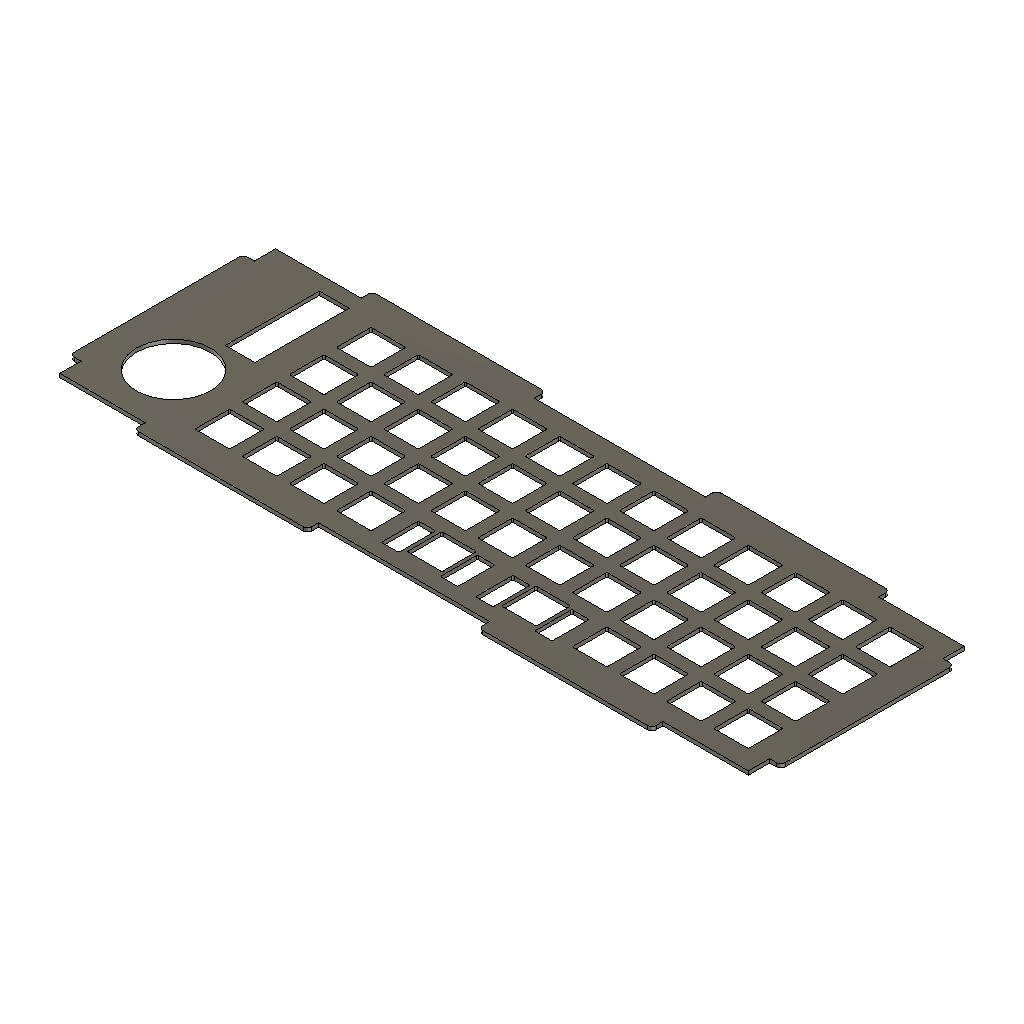
pcbPlate (Autodesk Fusion 360 design; units mm, degrees)
Autodesk Fusion 360 part; units mm, degrees
sketch "keyboard-plate" plane through (0, 0, 0) normal (0, 0, 1) x (1, 0, 0)
  line L0 (32.55, -57.15) -> (19.55, -57.15)
  arc A0 (57.65, -57.15) -> (57.15, -57.65) centre (57.65, -57.65) ccw
  line L1 (52.1, -70.65) -> (52.1, -57.65)
  line L2 (51.6, -57.15) -> (38.6, -57.15)
  line L3 (38.1, -57.65) -> (38.1, -70.65)
  arc A1 (57.15, -70.65) -> (57.65, -71.15) centre (57.65, -70.65) ccw
  arc A2 (38.6, -57.15) -> (38.1, -57.65) centre (38.6, -57.65) ccw
  line L4 (85.725, -57.65) -> (85.725, -70.65)
  line L5 (0, -57.65) -> (0, -70.65)
  arc A3 (19.05, -32.55) -> (19.55, -33.05) centre (19.55, -32.55) ccw
  arc A4 (70.65, -71.15) -> (71.15, -70.65) centre (70.65, -70.65) ccw
  line L6 (70.65, -57.15) -> (57.65, -57.15)
  arc A5 (19.55, -57.15) -> (19.05, -57.65) centre (19.55, -57.65) ccw
  arc A6 (52.1, -57.65) -> (51.6, -57.15) centre (51.6, -57.65) ccw
  line L7 (71.15, -70.65) -> (71.15, -57.65)
  line L8 (57.15, -57.65) -> (57.15, -70.65)
  line L9 (57.65, -71.15) -> (70.65, -71.15)
  arc A7 (71.15, -57.65) -> (70.65, -57.15) centre (70.65, -57.65) ccw
  line L10 (86.225, -71.15) -> (99.225, -71.15)
  arc A8 (99.725, -57.65) -> (99.225, -57.15) centre (99.225, -57.65) ccw
  arc A9 (19.05, -70.65) -> (19.55, -71.15) centre (19.55, -70.65) ccw
  arc A10 (85.725, -70.65) -> (86.225, -71.15) centre (86.225, -70.65) ccw
  arc A11 (0.5, -57.15) -> (0, -57.65) centre (0.5, -57.65) ccw
  arc A12 (38.1, -70.65) -> (38.6, -71.15) centre (38.6, -70.65) ccw
  line L11 (38.6, -71.15) -> (51.6, -71.15)
  arc A13 (99.225, -71.15) -> (99.725, -70.65) centre (99.225, -70.65) ccw
  line L12 (19.55, -71.15) -> (32.55, -71.15)
  line L13 (33.05, -70.65) -> (33.05, -57.65)
  arc A14 (33.05, -57.65) -> (32.55, -57.15) centre (32.55, -57.65) ccw
  arc A15 (32.55, -71.15) -> (33.05, -70.65) centre (32.55, -70.65) ccw
  line L14 (99.725, -70.65) -> (99.725, -57.65)
  line L15 (19.05, -57.65) -> (19.05, -70.65)
  arc A16 (51.6, -71.15) -> (52.1, -70.65) centre (51.6, -70.65) ccw
  arc A17 (165.9, -33.05) -> (166.4, -32.55) centre (165.9, -32.55) ccw
  line L16 (19.55, -33.05) -> (32.55, -33.05)
  arc A18 (51.6, -33.05) -> (52.1, -32.55) centre (51.6, -32.55) ccw
  arc A19 (89.7, -33.05) -> (90.2, -32.55) centre (89.7, -32.55) ccw
  line L17 (71.15, -32.55) -> (71.15, -19.55)
  line L18 (127.8, -19.05) -> (114.8, -19.05)
  arc A20 (166.4, -19.55) -> (165.9, -19.05) centre (165.9, -19.55) ccw
  line L19 (57.65, -33.05) -> (70.65, -33.05)
  arc A21 (95.25, -32.55) -> (95.75, -33.05) centre (95.75, -32.55) ccw
  line L20 (128.3, -32.55) -> (128.3, -19.55)
  arc A22 (114.8, -19.05) -> (114.3, -19.55) centre (114.8, -19.55) ccw
  line L21 (166.4, -32.55) -> (166.4, -19.55)
  arc A23 (133.35, -32.55) -> (133.85, -33.05) centre (133.85, -32.55) ccw
  line L22 (32.55, -19.05) -> (19.55, -19.05)
  arc A24 (146.85, -33.05) -> (147.35, -32.55) centre (146.85, -32.55) ccw
  line L23 (133.35, -19.55) -> (133.35, -32.55)
  line L24 (38.1, -19.55) -> (38.1, -32.55)
  arc A25 (33.05, -19.55) -> (32.55, -19.05) centre (32.55, -19.55) ccw
  line L25 (114.8, -33.05) -> (127.8, -33.05)
  arc A26 (128.3, -19.55) -> (127.8, -19.05) centre (127.8, -19.55) ccw
  arc A27 (108.75, -33.05) -> (109.25, -32.55) centre (108.75, -32.55) ccw
  line L26 (114.3, -19.55) -> (114.3, -32.55)
  arc A28 (52.1, -19.55) -> (51.6, -19.05) centre (51.6, -19.55) ccw
  line L27 (52.1, -32.55) -> (52.1, -19.55)
  line L28 (147.35, -32.55) -> (147.35, -19.55)
  line L29 (70.65, -19.05) -> (57.65, -19.05)
  line L30 (95.25, -19.55) -> (95.25, -32.55)
  line L31 (19.05, -19.55) -> (19.05, -32.55)
  line L32 (95.75, -33.05) -> (108.75, -33.05)
  line L33 (38.6, -33.05) -> (51.6, -33.05)
  arc A29 (114.3, -32.55) -> (114.8, -33.05) centre (114.8, -32.55) ccw
  arc A30 (147.35, -19.55) -> (146.85, -19.05) centre (146.85, -19.55) ccw
  line L34 (146.85, -19.05) -> (133.85, -19.05)
  line L35 (90.2, -32.55) -> (90.2, -19.55)
  arc A31 (38.1, -32.55) -> (38.6, -33.05) centre (38.6, -32.55) ccw
  arc A32 (71.15, -19.55) -> (70.65, -19.05) centre (70.65, -19.55) ccw
  arc A33 (127.8, -33.05) -> (128.3, -32.55) centre (127.8, -32.55) ccw
  arc A34 (0.5, -19.05) -> (0, -19.55) centre (0.5, -19.55) ccw
  arc A35 (19.55, -19.05) -> (19.05, -19.55) centre (19.55, -19.55) ccw
  arc A36 (95.75, -19.05) -> (95.25, -19.55) centre (95.75, -19.55) ccw
  line L36 (133.85, -33.05) -> (146.85, -33.05)
  arc A37 (133.85, -19.05) -> (133.35, -19.55) centre (133.85, -19.55) ccw
  line L37 (51.6, -19.05) -> (38.6, -19.05)
  arc A38 (152.4, -32.55) -> (152.9, -33.05) centre (152.9, -32.55) ccw
  line L38 (33.05, -32.55) -> (33.05, -19.55)
  arc A39 (57.15, -32.55) -> (57.65, -33.05) centre (57.65, -32.55) ccw
  line L39 (0, -19.55) -> (0, -32.55)
  line L40 (152.9, -33.05) -> (165.9, -33.05)
  line L41 (165.9, -19.05) -> (152.9, -19.05)
  line L42 (76.7, -33.05) -> (89.7, -33.05)
  line L43 (108.75, -19.05) -> (95.75, -19.05)
  arc A40 (32.55, -33.05) -> (33.05, -32.55) centre (32.55, -32.55) ccw
  line L44 (76.2, -19.55) -> (76.2, -32.55)
  line L45 (0, -38.6) -> (0, -51.6)
  arc A41 (19.05, -51.6) -> (19.55, -52.1) centre (19.55, -51.6) ccw
  arc A42 (223.05, -33.05) -> (223.55, -32.55) centre (223.05, -32.55) ccw
  line L46 (52.1, -51.6) -> (52.1, -38.6)
  arc A43 (185.45, -19.55) -> (184.95, -19.05) centre (184.95, -19.55) ccw
  line L47 (0.5, -52.1) -> (13.5, -52.1)
  arc A44 (90.2, -19.55) -> (89.7, -19.05) centre (89.7, -19.55) ccw
  arc A45 (52.1, -38.6) -> (51.6, -38.1) centre (51.6, -38.6) ccw
  line L48 (184.95, -19.05) -> (171.95, -19.05)
  line L49 (51.6, -38.1) -> (38.6, -38.1)
  line L50 (38.1, -38.6) -> (38.1, -51.6)
  arc A46 (57.15, -51.6) -> (57.65, -52.1) centre (57.65, -51.6) ccw
  arc A47 (109.25, -19.55) -> (108.75, -19.05) centre (108.75, -19.55) ccw
  arc A48 (13.5, -52.1) -> (14, -51.6) centre (13.5, -51.6) ccw
  line L51 (32.55, -38.1) -> (19.55, -38.1)
  line L52 (57.65, -52.1) -> (70.65, -52.1)
  arc A49 (38.6, -38.1) -> (38.1, -38.6) centre (38.6, -38.6) ccw
  line L53 (204, -19.05) -> (191, -19.05)
  arc A50 (90.2, -38.6) -> (89.7, -38.1) centre (89.7, -38.6) ccw
  line L54 (90.2, -51.6) -> (90.2, -38.6)
  arc A51 (171.45, -32.55) -> (171.95, -33.05) centre (171.95, -32.55) ccw
  arc A52 (184.95, -33.05) -> (185.45, -32.55) centre (184.95, -32.55) ccw
  arc A53 (76.7, -19.05) -> (76.2, -19.55) centre (76.7, -19.55) ccw
  line L55 (57.15, -19.55) -> (57.15, -32.55)
  arc A54 (19.55, -38.1) -> (19.05, -38.6) centre (19.55, -38.6) ccw
  arc A55 (191, -19.05) -> (190.5, -19.55) centre (191, -19.55) ccw
  line L56 (209.55, -19.55) -> (209.55, -32.55)
  arc A56 (57.65, -19.05) -> (57.15, -19.55) centre (57.65, -19.55) ccw
  arc A57 (190.5, -32.55) -> (191, -33.05) centre (191, -32.55) ccw
  line L57 (13.5, -38.1) -> (0.5, -38.1)
  line L58 (70.65, -38.1) -> (57.65, -38.1)
  arc A58 (33.05, -38.6) -> (32.55, -38.1) centre (32.55, -38.6) ccw
  arc A59 (204.5, -19.55) -> (204, -19.05) centre (204, -19.55) ccw
  arc A60 (76.2, -32.55) -> (76.7, -33.05) centre (76.7, -32.55) ccw
  line L59 (223.55, -32.55) -> (223.55, -19.55)
  line L60 (171.95, -33.05) -> (184.95, -33.05)
  line L61 (89.7, -19.05) -> (76.7, -19.05)
  line L62 (185.45, -32.55) -> (185.45, -19.55)
  arc A61 (70.65, -33.05) -> (71.15, -32.55) centre (70.65, -32.55) ccw
  arc A62 (223.55, -19.55) -> (223.05, -19.05) centre (223.05, -19.55) ccw
  line L63 (89.7, -38.1) -> (76.7, -38.1)
  arc A63 (171.95, -19.05) -> (171.45, -19.55) centre (171.95, -19.55) ccw
  line L64 (109.25, -32.55) -> (109.25, -19.55)
  arc A64 (89.7, -52.1) -> (90.2, -51.6) centre (89.7, -51.6) ccw
  arc A65 (0, -51.6) -> (0.5, -52.1) centre (0.5, -51.6) ccw
  arc A66 (38.6, -19.05) -> (38.1, -19.55) centre (38.6, -19.55) ccw
  line L65 (19.05, -38.6) -> (19.05, -51.6)
  arc A67 (38.1, -51.6) -> (38.6, -52.1) centre (38.6, -51.6) ccw
  line L66 (190.5, -19.55) -> (190.5, -32.55)
  arc A68 (51.6, -52.1) -> (52.1, -51.6) centre (51.6, -51.6) ccw
  line L67 (171.45, -19.55) -> (171.45, -32.55)
  arc A69 (32.55, -52.1) -> (33.05, -51.6) centre (32.55, -51.6) ccw
  line L68 (204.5, -32.55) -> (204.5, -19.55)
  arc A70 (57.65, -38.1) -> (57.15, -38.6) centre (57.65, -38.6) ccw
  line L69 (210.05, -33.05) -> (223.05, -33.05)
  arc A71 (152.9, -19.05) -> (152.4, -19.55) centre (152.9, -19.55) ccw
  arc A72 (209.55, -32.55) -> (210.05, -33.05) centre (210.05, -32.55) ccw
  arc A73 (190.5, -51.6) -> (191, -52.1) centre (191, -51.6) ccw
  arc A74 (147.35, -38.6) -> (146.85, -38.1) centre (146.85, -38.6) ccw
  line L70 (223.05, -38.1) -> (210.05, -38.1)
  arc A75 (210.05, -38.1) -> (209.55, -38.6) centre (210.05, -38.6) ccw
  line L71 (209.55, -38.6) -> (209.55, -51.6)
  line L72 (33.05, -51.6) -> (33.05, -38.6)
  line L73 (191, -33.05) -> (204, -33.05)
  arc A76 (76.2, -51.6) -> (76.7, -52.1) centre (76.7, -51.6) ccw
  arc A77 (204, -33.05) -> (204.5, -32.55) centre (204, -32.55) ccw
  arc A78 (171.45, -51.6) -> (171.95, -52.1) centre (171.95, -51.6) ccw
  arc A79 (109.25, -38.6) -> (108.75, -38.1) centre (108.75, -38.6) ccw
  arc A80 (210.05, -19.05) -> (209.55, -19.55) centre (210.05, -19.55) ccw
  line L74 (14, -51.6) -> (14, -38.6)
  arc A81 (0.5, -38.1) -> (0, -38.6) centre (0.5, -38.6) ccw
  line L75 (57.15, -38.6) -> (57.15, -51.6)
  line L76 (204, -38.1) -> (191, -38.1)
  line L77 (114.3, -38.6) -> (114.3, -51.6)
  line L78 (184.95, -38.1) -> (171.95, -38.1)
  arc A82 (114.3, -51.6) -> (114.8, -52.1) centre (114.8, -51.6) ccw
  line L79 (76.7, -52.1) -> (89.7, -52.1)
  line L80 (38.6, -52.1) -> (51.6, -52.1)
  arc A83 (204.5, -38.6) -> (204, -38.1) centre (204, -38.6) ccw
  line L81 (71.15, -51.6) -> (71.15, -38.6)
  line L82 (152.4, -19.55) -> (152.4, -32.55)
  arc A84 (171.95, -38.1) -> (171.45, -38.6) centre (171.95, -38.6) ccw
  arc A85 (152.9, -38.1) -> (152.4, -38.6) centre (152.9, -38.6) ccw
  arc A86 (70.65, -52.1) -> (71.15, -51.6) centre (70.65, -51.6) ccw
  line L83 (108.75, -38.1) -> (95.75, -38.1)
  arc A87 (191, -38.1) -> (190.5, -38.6) centre (191, -38.6) ccw
  line L84 (223.05, -19.05) -> (210.05, -19.05)
  line L85 (210.05, -52.1) -> (223.05, -52.1)
  arc A88 (71.15, -38.6) -> (70.65, -38.1) centre (70.65, -38.6) ccw
  arc A89 (14, -38.6) -> (13.5, -38.1) centre (13.5, -38.6) ccw
  line L86 (19.55, -52.1) -> (32.55, -52.1)
  line L87 (191, -52.1) -> (204, -52.1)
  arc A90 (133.35, -51.6) -> (133.85, -52.1) centre (133.85, -51.6) ccw
  arc A91 (128.3, -38.6) -> (127.8, -38.1) centre (127.8, -38.6) ccw
  arc A92 (95.25, -51.6) -> (95.75, -52.1) centre (95.75, -51.6) ccw
  line L88 (171.45, -38.6) -> (171.45, -51.6)
  arc A93 (223.55, -38.6) -> (223.05, -38.1) centre (223.05, -38.6) ccw
  arc A94 (127.8, -52.1) -> (128.3, -51.6) centre (127.8, -51.6) ccw
  arc A95 (184.95, -52.1) -> (185.45, -51.6) centre (184.95, -51.6) ccw
  arc A96 (114.8, -38.1) -> (114.3, -38.6) centre (114.8, -38.6) ccw
  arc A97 (204, -52.1) -> (204.5, -51.6) centre (204, -51.6) ccw
  arc A98 (51.6, -14) -> (52.1, -13.5) centre (51.6, -13.5) ccw
  line L89 (52.1, -13.5) -> (52.1, -0.5)
  line L90 (114.8, -52.1) -> (127.8, -52.1)
  arc A99 (52.1, -0.5) -> (51.6, 0) centre (51.6, -0.5) ccw
  line L91 (51.6, 0) -> (38.6, 0)
  arc A100 (133.85, -38.1) -> (133.35, -38.6) centre (133.85, -38.6) ccw
  arc A101 (38.6, 0) -> (38.1, -0.5) centre (38.6, -0.5) ccw
  line L92 (166.4, -51.6) -> (166.4, -38.6)
  arc A102 (0.5, 0) -> (0, -0.5) centre (0.5, -0.5) ccw
  line L93 (99.225, -57.15) -> (86.225, -57.15)
  line L94 (95.25, -38.6) -> (95.25, -51.6)
  arc A103 (165.9, -52.1) -> (166.4, -51.6) centre (165.9, -51.6) ccw
  arc A104 (14, -57.65) -> (13.5, -57.15) centre (13.5, -57.65) ccw
  arc A105 (13.5, -14) -> (14, -13.5) centre (13.5, -13.5) ccw
  line L95 (14, -70.65) -> (14, -57.65)
  arc A106 (38.1, -13.5) -> (38.6, -14) centre (38.6, -13.5) ccw
  line L96 (38.1, -0.5) -> (38.1, -13.5)
  line L97 (147.35, -51.6) -> (147.35, -38.6)
  line L98 (223.55, -51.6) -> (223.55, -38.6)
  line L99 (127.8, -38.1) -> (114.8, -38.1)
  line L100 (152.9, -52.1) -> (165.9, -52.1)
  line L101 (0.5, -71.15) -> (13.5, -71.15)
  line L102 (165.9, -38.1) -> (152.9, -38.1)
  arc A107 (19.05, -13.5) -> (19.55, -14) centre (19.55, -13.5) ccw
  line L103 (152.4, -38.6) -> (152.4, -51.6)
  line L104 (146.85, -38.1) -> (133.85, -38.1)
  line L105 (0, -0.5) -> (0, -13.5)
  line L106 (13.5, -57.15) -> (0.5, -57.15)
  arc A108 (0, -70.65) -> (0.5, -71.15) centre (0.5, -70.65) ccw
  line L107 (133.35, -38.6) -> (133.35, -51.6)
  arc A109 (32.55, -14) -> (33.05, -13.5) centre (32.55, -13.5) ccw
  arc A110 (0, -13.5) -> (0.5, -14) centre (0.5, -13.5) ccw
  arc A111 (185.45, -38.6) -> (184.95, -38.1) centre (184.95, -38.6) ccw
  line L108 (33.05, -13.5) -> (33.05, -0.5)
  line L109 (32.55, 0) -> (19.55, 0)
  line L110 (76.2, -38.6) -> (76.2, -51.6)
  arc A112 (209.55, -51.6) -> (210.05, -52.1) centre (210.05, -51.6) ccw
  arc A113 (13.5, -71.15) -> (14, -70.65) centre (13.5, -70.65) ccw
  arc A114 (76.7, -38.1) -> (76.2, -38.6) centre (76.7, -38.6) ccw
  line L111 (185.45, -51.6) -> (185.45, -38.6)
  arc A115 (86.225, -57.15) -> (85.725, -57.65) centre (86.225, -57.65) ccw
  line L112 (204.5, -51.6) -> (204.5, -38.6)
  arc A116 (95.75, -38.1) -> (95.25, -38.6) centre (95.75, -38.6) ccw
  arc A117 (152.4, -51.6) -> (152.9, -52.1) centre (152.9, -51.6) ccw
  line L113 (13.5, 0) -> (0.5, 0)
  line L114 (133.85, -52.1) -> (146.85, -52.1)
  line L115 (95.75, -52.1) -> (108.75, -52.1)
  line L116 (190.5, -38.6) -> (190.5, -51.6)
  line L117 (19.55, -14) -> (32.55, -14)
  line L118 (14, -13.5) -> (14, -0.5)
  arc A118 (14, -0.5) -> (13.5, 0) centre (13.5, -0.5) ccw
  line L119 (0.5, -14) -> (13.5, -14)
  arc A119 (33.05, -0.5) -> (32.55, 0) centre (32.55, -0.5) ccw
  arc A120 (19.55, 0) -> (19.05, -0.5) centre (19.55, -0.5) ccw
  arc A121 (146.85, -52.1) -> (147.35, -51.6) centre (146.85, -51.6) ccw
  arc A122 (166.4, -38.6) -> (165.9, -38.1) centre (165.9, -38.6) ccw
  line L120 (171.95, -52.1) -> (184.95, -52.1)
  arc A123 (223.05, -52.1) -> (223.55, -51.6) centre (223.05, -51.6) ccw
  line L121 (109.25, -51.6) -> (109.25, -38.6)
  line L122 (19.05, -0.5) -> (19.05, -13.5)
  line L123 (128.3, -51.6) -> (128.3, -38.6)
  arc A124 (108.75, -52.1) -> (109.25, -51.6) centre (108.75, -51.6) ccw
  line L124 (38.6, -14) -> (51.6, -14)
  arc A125 (114.3, -13.5) -> (114.8, -14) centre (114.8, -13.5) ccw
  arc A126 (165.9, -14) -> (166.4, -13.5) centre (165.9, -13.5) ccw
  line L125 (109.25, -13.5) -> (109.25, -0.5)
  arc A127 (13.5, -33.05) -> (14, -32.55) centre (13.5, -32.55) ccw
  line L126 (152.9, -14) -> (165.9, -14)
  line L127 (127.8, 0) -> (114.8, 0)
  arc A128 (171.45, -13.5) -> (171.95, -14) centre (171.95, -13.5) ccw
  line L128 (90.2, -13.5) -> (90.2, -0.5)
  line L129 (76.7, -14) -> (89.7, -14)
  arc A129 (89.7, -14) -> (90.2, -13.5) centre (89.7, -13.5) ccw
  line L130 (171.95, -14) -> (184.95, -14)
  line L131 (147.35, -13.5) -> (147.35, -0.5)
  line L132 (57.65, -14) -> (70.65, -14)
  arc A130 (190.5, -13.5) -> (191, -14) centre (191, -13.5) ccw
  arc A131 (108.75, -14) -> (109.25, -13.5) centre (108.75, -13.5) ccw
  line L133 (152.4, -0.5) -> (152.4, -13.5)
  arc A132 (57.15, -13.5) -> (57.65, -14) centre (57.65, -13.5) ccw
  arc A133 (109.25, -0.5) -> (108.75, 0) centre (108.75, -0.5) ccw
  line L134 (204.5, -13.5) -> (204.5, -0.5)
  line L135 (166.4, -13.5) -> (166.4, -0.5)
  arc A134 (90.2, -0.5) -> (89.7, 0) centre (89.7, -0.5) ccw
  line L136 (76.2, -0.5) -> (76.2, -13.5)
  line L137 (108.75, 0) -> (95.75, 0)
  line L138 (114.8, -14) -> (127.8, -14)
  line L139 (133.35, -0.5) -> (133.35, -13.5)
  arc A135 (184.95, -14) -> (185.45, -13.5) centre (184.95, -13.5) ccw
  line L140 (114.3, -0.5) -> (114.3, -13.5)
  arc A136 (57.65, 0) -> (57.15, -0.5) centre (57.65, -0.5) ccw
  arc A137 (76.2, -13.5) -> (76.7, -14) centre (76.7, -13.5) ccw
  line L141 (191, -14) -> (204, -14)
  arc A138 (95.75, 0) -> (95.25, -0.5) centre (95.75, -0.5) ccw
  line L142 (171.45, -0.5) -> (171.45, -13.5)
  arc A139 (70.65, -14) -> (71.15, -13.5) centre (70.65, -13.5) ccw
  line L143 (14, -32.55) -> (14, -19.55)
  arc A140 (166.4, -0.5) -> (165.9, 0) centre (165.9, -0.5) ccw
  arc A141 (14, -19.55) -> (13.5, -19.05) centre (13.5, -19.55) ccw
  arc A142 (204, -14) -> (204.5, -13.5) centre (204, -13.5) ccw
  line L144 (57.15, -0.5) -> (57.15, -13.5)
  line L145 (95.75, -14) -> (108.75, -14)
  line L146 (13.5, -19.05) -> (0.5, -19.05)
  line L147 (204, 0) -> (191, 0)
  line L148 (190.5, -0.5) -> (190.5, -13.5)
  arc A143 (127.8, -14) -> (128.3, -13.5) centre (127.8, -13.5) ccw
  arc A144 (128.3, -0.5) -> (127.8, 0) centre (127.8, -0.5) ccw
  line L149 (95.25, -0.5) -> (95.25, -13.5)
  arc A145 (191, 0) -> (190.5, -0.5) centre (191, -0.5) ccw
  arc A146 (71.15, -0.5) -> (70.65, 0) centre (70.65, -0.5) ccw
  line L150 (71.15, -13.5) -> (71.15, -0.5)
  arc A147 (204.5, -0.5) -> (204, 0) centre (204, -0.5) ccw
  line L151 (133.85, -14) -> (146.85, -14)
  line L152 (210.05, -14) -> (223.05, -14)
  arc A148 (223.05, -14) -> (223.55, -13.5) centre (223.05, -13.5) ccw
  arc A149 (171.95, 0) -> (171.45, -0.5) centre (171.95, -0.5) ccw
  arc A150 (223.55, -0.5) -> (223.05, 0) centre (223.05, -0.5) ccw
  arc A151 (209.55, -13.5) -> (210.05, -14) centre (210.05, -13.5) ccw
  arc A152 (146.85, -14) -> (147.35, -13.5) centre (146.85, -13.5) ccw
  arc A153 (95.25, -13.5) -> (95.75, -14) centre (95.75, -13.5) ccw
  line L153 (70.65, 0) -> (57.65, 0)
  arc A154 (76.7, 0) -> (76.2, -0.5) centre (76.7, -0.5) ccw
  arc A155 (114.8, 0) -> (114.3, -0.5) centre (114.8, -0.5) ccw
  line L154 (185.45, -13.5) -> (185.45, -0.5)
  line L155 (128.3, -13.5) -> (128.3, -0.5)
  line L156 (89.7, 0) -> (76.7, 0)
  line L157 (184.95, 0) -> (171.95, 0)
  arc A156 (166.4, -57.65) -> (165.9, -57.15) centre (165.9, -57.65) ccw
  arc A157 (137.825, -57.65) -> (137.325, -57.15) centre (137.325, -57.65) ccw
  arc A158 (122.387, -58.65) -> (121.887, -58.15) centre (121.887, -58.65) ccw
  line L158 (210.05, -71.15) -> (223.05, -71.15)
  arc A159 (115.387, -72.65) -> (115.887, -73.15) centre (115.887, -72.65) ccw
  arc A160 (210.05, -57.15) -> (209.55, -57.65) centre (210.05, -57.65) ccw
  arc A161 (133.85, 0) -> (133.35, -0.5) centre (133.85, -0.5) ccw
  arc A162 (152.9, 0) -> (152.4, -0.5) centre (152.9, -0.5) ccw
  line L159 (185.45, -70.65) -> (185.45, -57.65)
  arc A163 (209.55, -70.65) -> (210.05, -71.15) centre (210.05, -70.65) ccw
  arc A164 (121.887, -73.15) -> (122.387, -72.65) centre (121.887, -72.65) ccw
  arc A165 (152.4, -70.65) -> (152.9, -71.15) centre (152.9, -70.65) ccw
  arc A166 (0, -32.55) -> (0.5, -33.05) centre (0.5, -32.55) ccw
  line L160 (223.55, -70.65) -> (223.55, -57.65)
  line L161 (77.287, -58.65) -> (77.287, -72.65)
  arc A167 (84.287, -58.65) -> (83.787, -58.15) centre (83.787, -58.65) ccw
  line L162 (146.85, 0) -> (133.85, 0)
  arc A168 (171.95, -57.15) -> (171.45, -57.65) centre (171.95, -57.65) ccw
  arc A169 (137.325, -71.15) -> (137.825, -70.65) centre (137.325, -70.65) ccw
  line L163 (171.45, -57.65) -> (171.45, -70.65)
  arc A170 (204, -71.15) -> (204.5, -70.65) centre (204, -70.65) ccw
  line L164 (107.663, -58.15) -> (101.663, -58.15)
  arc A171 (204.5, -57.65) -> (204, -57.15) centre (204, -57.65) ccw
  arc A172 (223.05, -71.15) -> (223.55, -70.65) centre (223.05, -70.65) ccw
  arc A173 (184.95, -71.15) -> (185.45, -70.65) centre (184.95, -70.65) ccw
  line L165 (123.825, -57.65) -> (123.825, -70.65)
  arc A174 (101.663, -58.15) -> (101.163, -58.65) centre (101.663, -58.65) ccw
  line L166 (122.387, -72.65) -> (122.387, -58.65)
  line L167 (137.825, -70.65) -> (137.825, -57.65)
  line L168 (184.95, -57.15) -> (171.95, -57.15)
  arc A175 (108.163, -58.65) -> (107.663, -58.15) centre (107.663, -58.65) ccw
  line L169 (101.163, -58.65) -> (101.163, -72.65)
  line L170 (190.5, -57.65) -> (190.5, -70.65)
  line L171 (137.325, -57.15) -> (124.325, -57.15)
  line L172 (191, -71.15) -> (204, -71.15)
  arc A176 (152.9, -57.15) -> (152.4, -57.65) centre (152.9, -57.65) ccw
  arc A177 (77.287, -72.65) -> (77.787, -73.15) centre (77.787, -72.65) ccw
  arc A178 (133.35, -13.5) -> (133.85, -14) centre (133.85, -13.5) ccw
  line L173 (83.787, -58.15) -> (77.787, -58.15)
  line L174 (204, -57.15) -> (191, -57.15)
  arc A179 (107.663, -73.15) -> (108.163, -72.65) centre (107.663, -72.65) ccw
  line L175 (209.55, -0.5) -> (209.55, -13.5)
  line L176 (77.787, -73.15) -> (83.787, -73.15)
  line L177 (0.5, -33.05) -> (13.5, -33.05)
  line L178 (223.55, -13.5) -> (223.55, -0.5)
  arc A180 (124.325, -57.15) -> (123.825, -57.65) centre (124.325, -57.65) ccw
  line L179 (223.05, 0) -> (210.05, 0)
  line L180 (165.9, 0) -> (152.9, 0)
  line L181 (152.4, -57.65) -> (152.4, -70.65)
  arc A181 (171.45, -70.65) -> (171.95, -71.15) centre (171.95, -70.65) ccw
  arc A182 (185.45, -0.5) -> (184.95, 0) centre (184.95, -0.5) ccw
  arc A183 (77.787, -58.15) -> (77.287, -58.65) centre (77.787, -58.65) ccw
  line L182 (171.95, -71.15) -> (184.95, -71.15)
  arc A184 (210.05, 0) -> (209.55, -0.5) centre (210.05, -0.5) ccw
  line L183 (223.05, -57.15) -> (210.05, -57.15)
  arc A185 (185.45, -57.65) -> (184.95, -57.15) centre (184.95, -57.65) ccw
  arc A186 (152.4, -13.5) -> (152.9, -14) centre (152.9, -13.5) ccw
  arc A187 (191, -57.15) -> (190.5, -57.65) centre (191, -57.65) ccw
  arc A188 (223.55, -57.65) -> (223.05, -57.15) centre (223.05, -57.65) ccw
  line L184 (152.9, -71.15) -> (165.9, -71.15)
  line L185 (124.325, -71.15) -> (137.325, -71.15)
  arc A189 (147.35, -0.5) -> (146.85, 0) centre (146.85, -0.5) ccw
  arc A190 (123.825, -70.65) -> (124.325, -71.15) centre (124.325, -70.65) ccw
  line L186 (84.287, -72.65) -> (84.287, -58.65)
  arc A191 (139.763, -58.15) -> (139.263, -58.65) centre (139.763, -58.65) ccw
  arc A192 (83.787, -73.15) -> (84.287, -72.65) centre (83.787, -72.65) ccw
  arc A193 (146.263, -58.65) -> (145.763, -58.15) centre (145.763, -58.65) ccw
  arc A194 (190.5, -70.65) -> (191, -71.15) centre (191, -70.65) ccw
  arc A195 (165.9, -71.15) -> (166.4, -70.65) centre (165.9, -70.65) ccw
  line L187 (121.887, -58.15) -> (115.887, -58.15)
  arc A196 (101.163, -72.65) -> (101.663, -73.15) centre (101.663, -72.65) ccw
  line L188 (108.163, -72.65) -> (108.163, -58.65)
  line L189 (101.663, -73.15) -> (107.663, -73.15)
  line L190 (165.9, -57.15) -> (152.9, -57.15)
  line L191 (139.763, -73.15) -> (145.763, -73.15)
  arc A197 (145.763, -73.15) -> (146.263, -72.65) centre (145.763, -72.65) ccw
  line L192 (209.55, -57.65) -> (209.55, -70.65)
  line L193 (204.5, -70.65) -> (204.5, -57.65)
  line L194 (146.263, -72.65) -> (146.263, -58.65)
  arc A198 (115.887, -58.15) -> (115.387, -58.65) centre (115.887, -58.65) ccw
  line L195 (115.887, -73.15) -> (121.887, -73.15)
  line L196 (115.387, -58.65) -> (115.387, -72.65)
  arc A199 (139.263, -72.65) -> (139.763, -73.15) centre (139.763, -72.65) ccw
  line L197 (166.4, -70.65) -> (166.4, -57.65)
  line L198 (139.263, -58.65) -> (139.263, -72.65)
  line L199 (145.763, -58.15) -> (139.763, -58.15)
  circle A200 centre (-25.185, -54.65) radius 15
  line L200 (-23.132, 2.247) -> (-11.132, 2.247)
  line L201 (-11.132, 2.247) -> (-11.132, -35.753)
  line L202 (-11.132, -35.753) -> (-23.132, -35.753)
  line L203 (-23.132, -35.753) -> (-23.132, 2.247)
  line L204 (-46.785, -0.385) -> (-49.535, -0.385)
  line L205 (-51.285, -2.135) -> (-51.285, -68.635)
  line L206 (-49.535, -70.385) -> (-46.785, -70.385)
  line L207 (-46.785, -0.385) -> (-46.785, 8.2)
  line L208 (-46.785, -70.385) -> (-46.785, -78.97)
  arc A201 (-51.285, -68.635) -> (-49.535, -70.385) centre (-49.535, -68.635) ccw
  arc A202 (-49.535, -0.385) -> (-51.285, -2.135) centre (-49.535, -2.135) ccw
  line L209 (231.39, -70.385) -> (234.14, -70.385)
  line L210 (235.89, -68.635) -> (235.89, -2.135)
  line L211 (234.14, -0.385) -> (231.39, -0.385)
  line L212 (231.39, -70.385) -> (231.39, -78.97)
  line L213 (231.39, -0.385) -> (231.39, 8.2)
  arc A203 (234.14, -70.385) -> (235.89, -68.635) centre (234.14, -68.635) ccw
  arc A204 (235.89, -2.135) -> (234.14, -0.385) centre (234.14, -2.135) ccw
  line L214 (57.7588, 8.2) -> (57.7588, 10.95)
  line L215 (56.0088, 12.7) -> (-10.4912, 12.7)
  line L216 (-12.2412, 10.95) -> (-12.2412, 8.2)
  arc A205 (57.7588, 10.95) -> (56.0088, 12.7) centre (56.0088, 10.95) ccw
  arc A206 (-10.4912, 12.7) -> (-12.2412, 10.95) centre (-10.4912, 10.95) ccw
  line L217 (126.8463, 8.2) -> (126.8463, 10.95)
  line L218 (128.5963, 12.7) -> (195.0962, 12.7)
  line L219 (196.8463, 10.95) -> (196.8462, 8.2)
  arc A207 (128.5963, 12.7) -> (126.8463, 10.95) centre (128.5963, 10.95) ccw
  arc A208 (196.8463, 10.95) -> (195.0962, 12.7) centre (195.0962, 10.95) ccw
  line L220 (57.7587, -78.97) -> (57.7587, -81.72)
  line L221 (56.0087, -83.47) -> (-10.4913, -83.47)
  line L222 (-12.2413, -81.72) -> (-12.2413, -78.97)
  arc A209 (-12.2413, -81.72) -> (-10.4913, -83.47) centre (-10.4913, -81.72) ccw
  arc A210 (56.0087, -83.47) -> (57.7587, -81.72) centre (56.0087, -81.72) ccw
  line L223 (196.8462, -78.97) -> (196.8462, -81.72)
  line L224 (195.0962, -83.47) -> (128.5962, -83.47)
  line L225 (126.8462, -81.72) -> (126.8462, -78.97)
  arc A211 (126.8462, -81.72) -> (128.5962, -83.47) centre (128.5962, -81.72) ccw
  arc A212 (195.0962, -83.47) -> (196.8462, -81.72) centre (195.0962, -81.72) ccw
  line L226 (126.8462, -78.97) -> (92.3025, -78.97)
  line L227 (196.8462, -78.97) -> (231.39, -78.97)
  line L228 (92.3025, -78.97) -> (57.7587, -78.97)
  line L229 (-46.785, -78.97) -> (-12.2413, -78.97)
  line L230 (-46.785, 8.2) -> (-12.2412, 8.2)
  line L231 (57.7588, 8.2) -> (92.3025, 8.2)
  line L232 (92.3025, 8.2) -> (126.8463, 8.2)
  line L233 (196.8462, 8.2) -> (231.39, 8.2)
  line L234 (216.55, -57.15) -> (216.55, -71.15) construction
  line L235 (209.55, -64.15) -> (223.55, -64.15) construction
  line L236 (7, -19.05) -> (7, -33.05) construction
  point P0 (-51.285, -0.385)
  point P1 (-51.285, -70.385)
  point P2 (235.89, -70.385)
  point P3 (235.89, -0.385)
  point P4 (57.7588, 12.7)
  point P5 (-12.2412, 12.7)
  point P6 (196.8462, -83.47)
  point P7 (126.8462, -83.47)
  dimension "d7" = 30
  dimension "d9" = 12
  dimension "d12" = 4.5
  dimension "d13" = 70
  dimension "d14" = 1.75
  dimension "d15" = 1.75
  dimension "d20" = 70
  dimension "d21" = 1.75
  dimension "d22" = 1.75
  dimension "d23" = 4.5
  dimension "d24" = 4.5
  dimension "d25" = 278.175
  dimension "d26" = 21.6
  dimension "d27" = 4.5
  dimension "d28" = 70
  dimension "d29" = 1.75
  dimension "d30" = 1.75
  dimension "d31" = 70
  dimension "d33" = 1.75
  dimension "d34" = 1.75
  dimension "d35" = 1.75
  dimension "d36" = 1.75
  dimension "d38" = 70
  dimension "d39" = 4.5
  dimension "d40" = 70
  dimension "d41" = 1.75
  dimension "d42" = 1.75
  dimension "d51" = 4.5
  dimension "d52" = 24.32
  dimension "d53" = 14.84
  dimension "d54" = 14.82
  dimension "d55" = 72.35
  dimension "d56" = 38
  dimension "d57" = 18.132
  dimension "d58" = 5.953
  constraint horizontal L200
  constraint vertical L201
  constraint horizontal L202
  constraint vertical L203
  constraint horizontal L204
  constraint vertical L205
  constraint horizontal L206
  constraint equal L207 L208
  constraint coincident P1 L205
  constraint coincident P1 L206
  constraint tangent L205 A201
  constraint tangent L206 A201
  constraint coincident P0 L204
  constraint coincident P0 L205
  constraint tangent L204 A202
  constraint tangent L205 A202
  constraint perpendicular L158 L210
  constraint perpendicular L210 L211
  constraint perpendicular L209 L210
  constraint equal L212 L213
  constraint coincident P2 L210
  constraint coincident P2 L209
  constraint tangent L210 A203
  constraint tangent L209 A203
  constraint coincident P3 L211
  constraint coincident P3 L210
  constraint tangent L211 A204
  constraint tangent L210 A204
  constraint vertical L214
  constraint horizontal L215
  constraint vertical L216
  constraint coincident P4 L214
  constraint coincident P4 L215
  constraint tangent L214 A205
  constraint tangent L215 A205
  constraint coincident P5 L216
  constraint coincident P5 L215
  constraint tangent L216 A206
  constraint tangent L215 A206
  constraint vertical L217
  constraint horizontal L218
  constraint vertical L219
  constraint tangent L218 A207
  constraint tangent L217 A207
  constraint tangent L218 A208
  constraint tangent L219 A208
  constraint vertical L220
  constraint horizontal L221
  constraint vertical L222
  constraint tangent L222 A209
  constraint tangent L221 A209
  constraint tangent L220 A210
  constraint tangent L221 A210
  constraint vertical L223
  constraint horizontal L224
  constraint vertical L225
  constraint coincident P7 L225
  constraint coincident P7 L224
  constraint tangent L225 A211
  constraint tangent L224 A211
  constraint coincident P6 L224
  constraint coincident P6 L223
  constraint tangent L224 A212
  constraint tangent L223 A212
  constraint perpendicular L225 L226
  constraint collinear L215 L218
  constraint perpendicular L212 L227
  constraint perpendicular L220 L228
  constraint perpendicular L222 L229
  constraint perpendicular L216 L230
  constraint perpendicular L214 L231
  constraint perpendicular L217 L232
  constraint perpendicular L213 L233
  constraint midpoint L183 L234.start
  constraint midpoint L158 L234.end
  constraint midpoint L192 L235.start
  constraint midpoint L160 L235.end
  constraint collinear L227 L229
  constraint midpoint L146 L236.start
  constraint midpoint L177 L236.end
  constraint collinear L232 L233
  constraint collinear L230 L231
  constraint collinear L207 L208
  constraint equal L226 L228
  constraint equal L226 L227
  constraint equal L228 L229
  constraint equal L231 L232
  constraint equal L230 L231
  constraint equal L232 L233
  constraint collinear L226 L227
  measures "d7" diameter of A200
  measures "d9" distance of L201 L203
  measures "d12" distance of L204.start P0
  measures "d13" distance of P0 P1
  measures "d14" radius of A201
  measures "d15" radius of A202
  measures "d20" distance of P2 P3
  measures "d21" radius of A203
  measures "d22" radius of A204
  measures "d23" distance of L210 L213
  measures "d24" distance of L210 L212
  measures "d25" distance of L208 L212
  measures "d26" distance of A200.centre L208
  measures "d27" distance of L216.end P5
  measures "d28" distance of P4 P5
  measures "d29" radius of A205
  measures "d30" radius of A206
  measures "d31" distance of L217 L219
  measures "d33" radius of A207
  measures "d34" radius of A208
  measures "d35" radius of A209
  measures "d36" radius of A210
  measures "d38" distance of L220 L222
  measures "d39" distance of L225.end P7
  measures "d40" distance of P6 P7
  measures "d41" radius of A211
  measures "d42" radius of A212
  measures "d51" distance of L221 L229
  measures "d52" distance of A200.centre L229
  measures "d53" distance of L212 L234
  measures "d54" distance of L227 L235
  measures "d55" distance of L233 L235
  measures "d56" distance of L200 L202
  measures "d57" distance of L201 L236
  measures "d58" distance of L200 L230
extrude "Extrude1" add sketch "keyboard-plate" along normal blind 1.5
equation "d12 = 3.5 mm + 1 mm"
equation "d14 = ( 3.5 / 2 ) * 1 mm"
equation "d15 = ( 3.5 / 2 ) * 1 mm"
equation "d21 = ( 3.5 / 2 ) * 1 mm"
equation "d22 = ( 3.5 / 2 ) * 1 mm"
equation "d24 = 3.5 mm + 1 mm"
equation "d29 = ( 3.5 / 2 ) * 1 mm"
equation "d30 = ( 3.5 / 2 ) * 1 mm"
equation "d33 = ( 3.5 / 2 ) * 1 mm"
equation "d34 = ( 3.5 / 2 ) * 1 mm"
equation "d35 = ( 3.5 / 2 ) * 1 mm"
